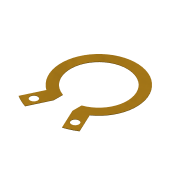
# Autodesk Inventor part: carbonpath
Saved by Autodesk Inventor 2015 SP1 (Build 190203100, 203)
## iProperties
Created: 2015-06-24
Part Number: carbonpath
Material: Generic
Document SubType Name: Modeling
Designer: Peter Mulkers
Density: 1 g/cm^3
Appearance: Weld - Brass
Author: Peter Mulkers
Autodesk Inventor part; units mm, degrees
ref_plane "YZ Plane" through (0, 0, 0) normal (1, 0, 0) x (0, 1, 0)
ref_plane "XZ Plane" through (0, 0, 0) normal (0, 1, 0) x (-1, 0, 0)
ref_plane "XY Plane" through (0, 0, 0) normal (0, 0, 1) x (1, 0, 0)
sketch "Sketch2" plane through (0, 0, 0) normal (0, 0, 1) x (1, 0, 0)
  arc A0 (2.5, -7.0711) -> (-2.5, -7.0711) centre (0, 0) ccw
  line L0 (0, -19.7448) -> (0, 14.9575) construction
  circle A1 centre (-5.494, -11.782) radius 1
  line L1 (-5.494, -11.782) -> (0, 0) construction
  line L2 (5.494, -11.782) -> (0, 0) construction
  arc A2 (-8.0947, -13.2184) -> (-4.9227, -14.6975) centre (0, 0) ccw
  line L3 (-5.747, -8.1836) -> (-8.0947, -13.2184)
  circle A3 centre (5.494, -11.782) radius 1
  arc A4 (4.9227, -14.6975) -> (8.0947, -13.2184) centre (0, 0) ccw
  line L4 (5.747, -8.1836) -> (8.0947, -13.2184)
  arc A5 (5.747, -8.1836) -> (-5.747, -8.1836) centre (0, 0) ccw
  line L5 (-2.5, -7.0711) -> (-2.5, -9.5021)
  line L6 (2.5, -7.0711) -> (2.5, -9.5021)
  line L7 (-4.9227, -14.6975) -> (-2.5, -9.5021)
  line L8 (4.9227, -14.6975) -> (2.5, -9.5021)
  dimension "d31" = 15
  dimension "d33" = 2
  dimension "d34" = 13
  dimension "d35" = 25
  dimension "d38" = 15.5
  dimension "d40" = 10
  dimension "d42" = 2.5
  dimension "d43" = 1.75
  dimension "d44" = 1.75
  constraints: 16 end point, 8 point on circle, 6 centre point, 6 symmetric about line, 3 coincident, 2 parallel, 2 vertical, 2 other
  measures "d31" diameter of A0
  measures "d33" diameter of A1
  measures "d34" distance of L1.start L1.end
  measures "d35" angle of L0 L1
  measures "d38" radius of A2
  measures "d40" radius of A5
  measures "d42" distance between parallel lines of L0 L5
  measures "d43" distance between parallel lines of L7 L1
  measures "d44" distance between parallel lines of L3 L1
extrude "Extrusion1" add sketch "Sketch2" along normal blind 0.1
body "Solid1"
